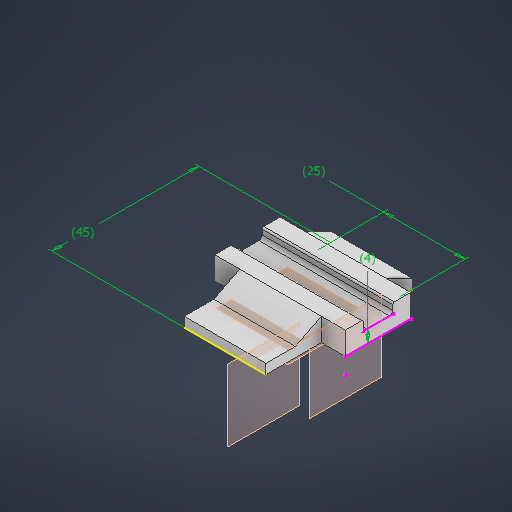
# Autodesk Inventor part: PartV4
Saved by Autodesk Inventor 2026 (Build 300175000, 175)
## iProperties
Created: 2026-10-27
Part Number: PartV4
Material: Generic
Document SubType Name: Modeling
Designer: alexp
Density: 1 g/cm^3
Appearance: Default
Author: alexp
Autodesk Inventor part; units mm, degrees
ref_plane "YZ Plane" through (0, 0, 0) normal (1, 0, 0) x (0, 1, 0)
ref_plane "XZ Plane" through (0, 0, 0) normal (0, 1, 0) x (-1, 0, 0)
ref_plane "XY Plane" through (0, 0, 0) normal (0, 0, 1) x (1, 0, 0)
ref_plane "Work Plane4" through (0, 5, 0) normal (0, 1, 0) x (1, 0, 0)
sketch "Sketch2" plane through (0, 5, 0) normal (0, 1, 0) x (1, 0, 0)
  point P0 (0, 0)
ref_plane "Work Plane2" through (0, 5, 0) normal (0, 1, 0) x (1, 0, 0)
sketch "Sketch4" plane through (0, 5, 0) normal (0, 1, 0) x (1, 0, 0)
  point P0 (0, 0)
ref_plane "Work Plane7" through (0, 5, 0) normal (0, 1, 0) x (1, 0, 0)
sketch "Sketch5" plane through (0, 5, 0) normal (0, 1, 0) x (1, 0, 0)
  line L0 (-22.3586, 20.0483) -> (17.6414, 20.0483)
  line L1 (17.6414, 20.0483) -> (17.6414, 0.0483)
  line L2 (17.6414, 0.0483) -> (-22.3586, 0.0483)
  line L3 (-22.3586, 0.0483) -> (-22.3586, 20.0483)
  line L4 (7.6414, 25.0483) -> (-12.3586, 25.0483) projected
  line L5 (-12.3586, 25.0483) -> (-12.3586, -14.9517) projected
  line L6 (7.6414, -14.9517) -> (7.6414, 25.0483) projected
  point P0 (0, 0)
  dimension "d4" = 20
  dimension "d5" = 5
  dimension "d6" = 10
  dimension "d7" = 10
  constraints: 8 end point, 2 parallel, 1 horizontal, 1 perpendicular
  measures "d4" distance between parallel lines of L2 L0
  measures "d5" distance between parallel lines of L0 L4
  measures "d6" distance between parallel lines of L3 L5
  measures "d7" distance between parallel lines of L1 L6
ref_plane "Work Plane1" through (7.6414, 0, 14.9517) normal (1, 0, 0) x (0, 0, -1)
extrude "Extrusion2" add sketch "Sketch5" along normal blind 4 contours L0 L5 L2 L3 | L0 L6 L2 L5 | L0 L1 L2 L6
sketch "Sketch7" plane through (-22.3586, 5, -20.0483) normal (-1, 0, 0) x (0, 0, 1)
  point P0 (20.0483, -5)
ref_plane "Work Plane6" through (0, 9, 0) normal (0, 1, 0) x (1, 0, 0)
sketch "Sketch8" plane through (0, 9, 0) normal (0, 1, 0) x (1, 0, 0)
  line L0 (17.6414, 0.0483) -> (17.6414, 20.0483) projected
  line L1 (-22.3586, 20.0483) -> (17.6414, 20.0483)
  line L2 (17.6414, 20.0483) -> (17.6414, 14.5483)
  line L3 (17.6414, 14.5483) -> (-22.3586, 14.5483)
  line L4 (-22.3586, 14.5483) -> (-22.3586, 20.0483)
  line L5 (-22.3586, 0.0483) -> (-12.3586, 0.0483) projected
  line L6 (-22.3586, 0.0483) -> (17.6414, 0.0483)
  line L7 (17.6414, 0.0483) -> (17.6414, 5.5483)
  line L8 (17.6414, 5.5483) -> (-22.3586, 5.5483)
  line L9 (-22.3586, 5.5483) -> (-22.3586, 0.0483)
  point P0 (0, 0)
  dimension "d11" = 5.5
  dimension "d12" = 5.5
  dimension "d13" = 9
  constraints: 16 end point, 4 parallel, 2 horizontal, 2 perpendicular, 2 point on line
  measures "d11" distance between parallel lines of L3 L1
  measures "d12" distance between parallel lines of L6 L8
  measures "d13" distance between parallel lines of L8 L3
extrude "Extrusion3" add sketch "Sketch8" along normal blind 3
sketch "Sketch9" plane through (0, 5, 0) normal (0, -1, 0) x (1, 0, 0)
  point P0 (0, 0)
ref_plane "Work Plane8" through (17.6414, 5, -0.0483) normal (1, 0, 0) x (0, 0, -1)
sketch "Sketch10" plane through (17.6414, 5, -0.0483) normal (1, 0, 0) x (0, 0, -1)
  line L0 (5.5, 4) -> (14.5, 4) projected
  line L1 (0, 0) -> (20, 0) projected
  point P0 (-0.0483, -5)
  dimension "d21" = 4
  measures "d21" distance between parallel lines of L0 L1
sketch "Sketch12" plane through (0, 5, 0) normal (0, -1, 0) x (1, 0, 0)
  line L0 (10.1414, -28.0483) -> (-14.8586, -28.0483)
  line L1 (-14.8586, -28.0483) -> (-14.8586, 16.9517)
  line L2 (-14.8586, 16.9517) -> (10.1414, 16.9517)
  line L3 (10.1414, 16.9517) -> (10.1414, -28.0483)
  line L4 (17.6414, -20.0483) -> (-22.3586, -20.0483) projected
  line L5 (17.6414, -0.0483) -> (17.6414, -20.0483) projected
  line L6 (-22.3586, -20.0483) -> (-22.3586, -0.0483) projected
  point P0 (0, 0)
  point P1 (10.1414, -20.0483)
  point P2 (-14.8586, -20.0483)
  dimension "d27" = 8
  dimension "d28" = 25
  dimension "d29" = 45
  dimension "d30" = 7.5
  dimension "d31" = 7.5
  constraints: 8 end point, 2 parallel, 1 horizontal, 1 perpendicular
  measures "d27" distance between parallel lines of L4 L0
  measures "d28" distance between parallel lines of L1 L3
  measures "d29" distance between parallel lines of L0 L2
  measures "d30" distance between parallel lines of L5 L3
  measures "d31" distance between parallel lines of L6 L1
sketch "Sketch13" plane through (0, 5, 0) normal (0, -1, 0) x (1, 0, 0)
  line L0 (-22.3586, -0.0483) -> (17.6414, -0.0483) projected
  line L1 (10.2894, -0.0483) -> (-14.7106, -0.0483)
  line L2 (-14.7106, -0.0483) -> (-14.7106, 16.9517)
  line L3 (-14.7106, 16.9517) -> (10.2894, 16.9517)
  line L4 (10.2894, 16.9517) -> (10.2894, -0.0483)
  point P0 (0, 0)
  point P1 (10.2894, 8.4517)
  dimension "d34" = 25
  dimension "d35" = 17
  constraints: 8 end point, 2 parallel, 1 horizontal, 1 midpoint, 1 perpendicular, 1 point on line
  measures "d34" distance from line of L2 point (10.289, 8.452)
  measures "d35" distance between parallel lines of L3 L0
extrude "Extrusion5" add sketch "Sketch13" against normal blind 3
extrude "Extrusion6" add sketch "Sketch12" against normal blind 3 contours L0 L1 L4 L3
sketch "Sketch14" plane through (0, 5, 0) normal (0, -1, 0) x (1, 0, 0)
  line L0 (-14.8586, -20.0483) -> (-14.8586, -28.0483) projected
  line L1 (10.1414, -28.0483) -> (10.1414, -20.0483) projected
  line L2 (10.2894, 16.9517) -> (-14.7106, 16.9517) projected
  line L3 (-14.8586, -28.0483) -> (10.1414, -28.0483) projected
  point P0 (0, 0)
  point P1 (-14.8586, -24.0483)
  point P2 (10.1414, -24.0483)
  dimension "d40" = 25
  dimension "d41" = 45
  constraints: 2 midpoint
  measures "d40" distance of point (-14.859, -24.048) point (10.141, -24.048)
  measures "d41" distance between parallel lines of L2 L3
sketch "Sketch15" plane through (10.1414, 5, -20.0483) normal (1, 0, 0) x (0, 0, -1)
  line L0 (0, 3) -> (8, 3) projected
  line L1 (-5.5, 7) -> (0, 7) projected
  line L2 (8, 3) -> (0, 7)
  line L3 (0, 7) -> (0, 3)
  point P0 (-20.0483, -5)
  constraints: 4 end point, 1 perpendicular
extrude "Extrusion7" add sketch "Sketch15" against normal blind 25
sketch "Sketch17" plane through (10.2894, 5, 16.9517) normal (1, 0, 0) x (0, 0, -1)
  line L0 (22.5, 7) -> (17, 7) projected
  line L1 (17, 7) -> (17, 3)
  line L2 (17, 3) -> (9.0372, 3)
  line L3 (9.0372, 3) -> (17, 7)
  point P0 (16.9517, -5)
  constraints: 6 end point, 1 perpendicular
extrude "Extrusion8" add sketch "Sketch17" against normal blind 25
fillet "Fillet7" radius 1 2 edges at (-2.3586, 9, -5.5483) (-2.3586, 9, -14.5483)
fillet "Fillet8" radius 0.5 2 edges at (-2.3586, 12, -5.5483) (-2.3586, 12, -14.5483)
body "Solid1"
